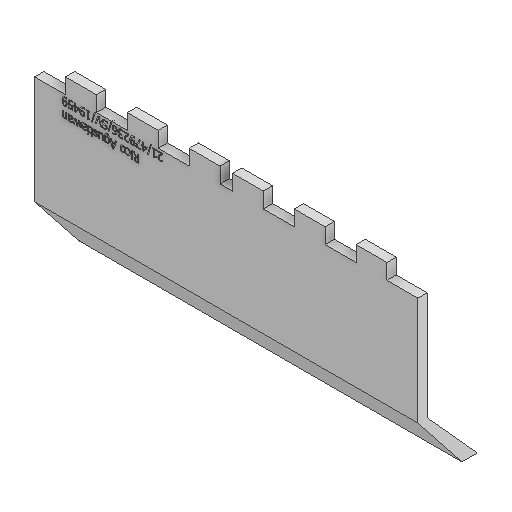
# Autodesk Inventor part: BodyFront
Saved by Autodesk Inventor 2025.2 (Build 292293000, 293)
## iProperties
Created: 2025-06-25
Part Number: BodyFront
Material: Generic
Document SubType Name: Modeling
Designer: ricoa
Density: 1 g/cm^3
Appearance: Default
Author: ricoa
Autodesk Inventor part; units mm, degrees
ref_plane "YZ Plane" through (0, 0, 0) normal (1, 0, 0) x (0, 1, 0)
ref_plane "XZ Plane" through (0, 0, 0) normal (0, 1, 0) x (-1, 0, 0)
sketch "Sketch1" plane through (0, 0, 0) normal (0, 0, 1) x (1, 0, 0)
  line L0 (104, 5) -> (114, 5) projected
  line L1 (84, 5) -> (94, 5) projected
  line L2 (94, 0) -> (104, 0) projected
  line L3 (74, 0) -> (84, 0) projected
  line L4 (64, 5) -> (74, 5) projected
  line L5 (60, 0) -> (64, 0) projected
  line L6 (50, 5) -> (60, 5) projected
  line L7 (40, 0) -> (50, 0) projected
  line L8 (30, 5) -> (40, 5) projected
  line L9 (20, 0) -> (30, 0) projected
  line L10 (10, 5) -> (20, 5) projected
  line L11 (0, 0) -> (10, 0) projected
  line L12 (10, 0) -> (10, 5) projected
  line L13 (20, 5) -> (20, 0) projected
  line L14 (30, 0) -> (30, 5) projected
  line L15 (40, 5) -> (40, 0) projected
  line L16 (50, 0) -> (50, 5) projected
  line L17 (60, 5) -> (60, 0) projected
  line L18 (64, 0) -> (64, 5) projected
  line L19 (84, 0) -> (84, 5) projected
  line L20 (94, 5) -> (94, 0) projected
  line L21 (104, 0) -> (104, 5) projected
  line L22 (114, 5) -> (114, 0) projected
  line L23 (114, 0) -> (124, 0) projected
  line L24 (124, 0) -> (124, -30)
  line L25 (0, -30) -> (0, 0)
  line L26 (74, 5) -> (74, 0) projected
  line L27 (0, -15) -> (124, -15) construction
  line L28 (104, -35) -> (114, -35)
  line L29 (84, -35) -> (94, -35)
  line L30 (94, -30) -> (104, -30)
  line L31 (74, -30) -> (84, -30)
  line L32 (64, -35) -> (74, -35)
  line L33 (60, -30) -> (64, -30)
  line L34 (50, -35) -> (60, -35)
  line L35 (40, -30) -> (50, -30)
  line L36 (30, -35) -> (40, -35)
  line L37 (20, -30) -> (30, -30)
  line L38 (10, -35) -> (20, -35)
  line L39 (0, -30) -> (10, -30)
  line L40 (10, -30) -> (10, -35)
  line L41 (20, -35) -> (20, -30)
  line L42 (30, -30) -> (30, -35)
  line L43 (40, -35) -> (40, -30)
  line L44 (50, -30) -> (50, -35)
  line L45 (60, -35) -> (60, -30)
  line L46 (64, -30) -> (64, -35)
  line L47 (84, -30) -> (84, -35)
  line L48 (94, -35) -> (94, -30)
  line L49 (104, -30) -> (104, -35)
  line L50 (114, -35) -> (114, -30)
  line L51 (114, -30) -> (124, -30)
  line L52 (74, -35) -> (74, -30)
  dimension "d0" = 30
  constraints: 56 end point, 24 symmetric about line, 2 midpoint, 1 vertical
  measures "d0" distance of L23.end L24.end
extrude "Extrusion1" add sketch "Sketch1" against normal blind 3
sketch "Sketch2" plane through (0, 0, 0) normal (0, 0, 1) x (1, 0, 0)
  line L0 (124, -30) -> (124, 0) projected
  line L1 (0, -30) -> (0, 0) projected
  line L2 (124, -30) -> (0, -30)
  line L3 (132.7341, -7.4829) -> (8.7341, -7.4829) construction
  line L4 (8.7341, -7.4829) -> (8.7341, -37.4829) construction
  line L5 (8.7341, -37.4829) -> (132.7341, -37.4829) construction
  line L6 (132.7341, -37.4829) -> (132.7341, -7.4829) construction
  line L7 (31.7814, -4.9264) -> (32.2199, -4.9264)
  line L8 (32.2199, -4.9264) -> (33.0226, -5.9371)
  line L9 (33.0226, -5.9371) -> (33.4096, -5.9371)
  line L10 (33.4096, -5.9371) -> (33.4096, -4.9264)
  line L11 (33.4096, -4.9264) -> (33.7472, -4.9264)
  line L12 (33.7472, -4.9264) -> (33.7472, -7.4664)
  line L13 (33.7472, -7.4664) -> (33.0926, -7.4664)
  spline S0 degree 2 poles (33.0926, -7.4664) (32.8744, -7.4664) (32.5801, -7.4191) (32.4463, -7.3326) knots 0 0 0 1 2 2 2
  spline S1 degree 2 poles (32.4463, -7.3326) (32.3125, -7.2462) (32.1581, -6.9765) (32.1581, -6.7769) knots 0 0 0 1 2 2 2
  spline S2 degree 2 poles (32.1581, -6.7769) (32.1581, -6.499) (32.4422, -6.1223) (32.685, -6.0318) knots 0 0 0 1 2 2 2
  line L14 (32.685, -6.0318) -> (31.7814, -4.9264)
  spline S3 degree 2 poles (32.5101, -6.7501) (32.5101, -6.8613) (32.5883, -7.0321) (32.6706, -7.0877) knots 0 0 0 1 2 2 2
  spline S4 degree 2 poles (32.6706, -7.0877) (32.7427, -7.135) (32.9341, -7.1741) (33.0741, -7.1741) knots 0 0 0 1 2 2 2
  line L15 (33.0741, -7.1741) -> (33.4096, -7.1741)
  line L16 (33.4096, -7.1741) -> (33.4096, -6.2191)
  line L17 (33.4096, -6.2191) -> (33.1132, -6.2191)
  spline S5 degree 2 poles (33.1132, -6.2191) (32.967, -6.2191) (32.7344, -6.2705) (32.6542, -6.3508) knots 0 0 0 1 2 2 2
  spline S6 degree 2 poles (32.6542, -6.3508) (32.5801, -6.4208) (32.5101, -6.6184) (32.5101, -6.7501) knots 0 0 0 1 2 2 2
  line L18 (31.2771, -4.9264) -> (31.5982, -4.9264)
  line L19 (31.5982, -4.9264) -> (31.5982, -6.8325)
  line L20 (31.5982, -6.8325) -> (31.2771, -6.8325)
  line L21 (31.2771, -6.8325) -> (31.2771, -4.9264)
  line L22 (31.2545, -7.1494) -> (31.6188, -7.1494)
  line L23 (31.6188, -7.1494) -> (31.6188, -7.4829)
  line L24 (31.6188, -7.4829) -> (31.2545, -7.4829)
  line L25 (31.2545, -7.4829) -> (31.2545, -7.1494)
  spline S7 degree 2 poles (30.0483, -4.8832) (30.2459, -4.8832) (30.5732, -5.0046) (30.6905, -5.1281) knots 0 0 0 1 2 2 2
  spline S8 degree 2 poles (30.6905, -5.1281) (30.8078, -5.2496) (30.9375, -5.6242) (30.9375, -5.8753) knots 0 0 0 1 2 2 2
  spline S9 degree 2 poles (30.9375, -5.8753) (30.9375, -6.1264) (30.8037, -6.4928) (30.6905, -6.6163) knots 0 0 0 1 2 2 2
  spline S10 degree 2 poles (30.6905, -6.6163) (30.5773, -6.7419) (30.2418, -6.8757) (30.0483, -6.8757) knots 0 0 0 1 2 2 2
  spline S11 degree 2 poles (30.0483, -6.8757) (29.8919, -6.8757) (29.5996, -6.7872) (29.4864, -6.7295) knots 0 0 0 1 2 2 2
  line L26 (29.4864, -6.7295) -> (29.4864, -6.3693)
  line L27 (29.4864, -6.3693) -> (29.5049, -6.3693)
  spline S12 degree 2 poles (29.5049, -6.3693) (29.5399, -6.3981) (29.6469, -6.4722) (29.7231, -6.5114) knots 0 0 0 1 2 2 2
  spline S13 degree 2 poles (29.7231, -6.5114) (29.791, -6.5443) (29.9721, -6.5957) (30.0545, -6.5957) knots 0 0 0 1 2 2 2
  spline S14 degree 2 poles (30.0545, -6.5957) (30.3035, -6.5957) (30.6061, -6.2191) (30.6061, -5.8753) knots 0 0 0 1 2 2 2
  spline S15 degree 2 poles (30.6061, -5.8753) (30.6061, -5.5398) (30.3138, -5.1631) (30.0545, -5.1631) knots 0 0 0 1 2 2 2
  spline S16 degree 2 poles (30.0545, -5.1631) (29.898, -5.1631) (29.614, -5.2928) (29.5049, -5.3937) knots 0 0 0 1 2 2 2
  line L28 (29.5049, -5.3937) -> (29.4864, -5.3937)
  line L29 (29.4864, -5.3937) -> (29.4864, -5.0335)
  spline S17 degree 2 poles (29.4864, -5.0335) (29.5337, -5.0108) (29.6778, -4.947) (29.7354, -4.9326) knots 0 0 0 1 2 2 2
  spline S18 degree 2 poles (29.7354, -4.9326) (29.8178, -4.9079) (29.9474, -4.8832) (30.0483, -4.8832) knots 0 0 0 1 2 2 2
  spline S19 degree 2 poles (27.6277, -5.8794) (27.6277, -5.3978) (28.0908, -4.8729) (28.4778, -4.8729) knots 0 0 0 1 2 2 2
  spline S20 degree 2 poles (28.4778, -4.8729) (28.875, -4.8729) (29.3299, -5.4143) (29.3299, -5.8794) knots 0 0 0 1 2 2 2
  spline S21 degree 2 poles (29.3299, -5.8794) (29.3299, -6.357) (28.8606, -6.886) (28.4778, -6.886) knots 0 0 0 1 2 2 2
  spline S22 degree 2 poles (28.4778, -6.886) (28.0908, -6.886) (27.6277, -6.359) (27.6277, -5.8794) knots 0 0 0 1 2 2 2
  spline S23 degree 2 poles (27.9591, -5.8794) (27.9591, -6.2499) (28.2287, -6.6102) (28.4778, -6.6102) knots 0 0 0 1 2 2 2
  spline S24 degree 2 poles (28.4778, -6.6102) (28.7268, -6.6102) (28.9986, -6.2499) (28.9986, -5.8794) knots 0 0 0 1 2 2 2
  spline S25 degree 2 poles (28.9986, -5.8794) (28.9986, -5.5192) (28.7268, -5.1487) (28.4778, -5.1487) knots 0 0 0 1 2 2 2
  spline S26 degree 2 poles (28.4778, -5.1487) (28.2308, -5.1487) (27.9591, -5.5131) (27.9591, -5.8794) knots 0 0 0 1 2 2 2
  line L30 (26.4565, -4.9264) -> (25.6002, -7.4664)
  line L31 (25.6002, -7.4664) -> (25.1844, -7.4664)
  line L32 (25.1844, -7.4664) -> (24.3282, -4.9264)
  line L33 (24.3282, -4.9264) -> (24.6843, -4.9264)
  line L34 (24.6843, -4.9264) -> (24.9148, -5.6366)
  line L35 (24.9148, -5.6366) -> (25.8843, -5.6366)
  line L36 (25.8843, -5.6366) -> (26.1148, -4.9264)
  line L37 (26.1148, -4.9264) -> (26.4565, -4.9264)
  line L38 (25.0074, -5.9247) -> (25.4006, -7.1206)
  line L39 (25.4006, -7.1206) -> (25.7916, -5.9247)
  line L40 (25.7916, -5.9247) -> (25.0074, -5.9247)
  spline S27 degree 2 poles (24.0441, -4.6218) (24.0112, -4.6074) (23.8856, -4.5621) (23.8053, -4.5436) knots 0 0 0 1 2 2 2
  spline S28 degree 2 poles (23.8053, -4.5436) (23.7168, -4.5209) (23.5666, -4.4942) (23.4781, -4.4942) knots 0 0 0 1 2 2 2
  spline S29 degree 2 poles (23.4781, -4.4942) (23.3299, -4.4942) (23.124, -4.5724) (23.0664, -4.6424) knots 0 0 0 1 2 2 2
  spline S30 degree 2 poles (23.0664, -4.6424) (23.0108, -4.7124) (22.9676, -4.8956) (22.9676, -5.0129) knots 0 0 0 1 2 2 2
  line L41 (22.9676, -5.0129) -> (22.9676, -5.1796)
  spline S31 degree 2 poles (22.9676, -5.1796) (23.0973, -5.0664) (23.3463, -4.9594) (23.5336, -4.9594) knots 0 0 0 1 2 2 2
  spline S32 degree 2 poles (23.5336, -4.9594) (23.8589, -4.9594) (24.2438, -5.4431) (24.2438, -5.898) knots 0 0 0 1 2 2 2
  spline S33 degree 2 poles (24.2438, -5.898) (24.2438, -6.1347) (24.11, -6.5011) (23.9988, -6.6307) knots 0 0 0 1 2 2 2
  spline S34 degree 2 poles (23.9988, -6.6307) (23.8918, -6.7522) (23.5974, -6.886) (23.441, -6.886) knots 0 0 0 1 2 2 2
  spline S35 degree 2 poles (23.441, -6.886) (23.2928, -6.886) (23.0767, -6.816) (22.9676, -6.7522) knots 0 0 0 1 2 2 2
  line L42 (22.9676, -6.7522) -> (22.9491, -6.8325)
  line L43 (22.9491, -6.8325) -> (22.6465, -6.8325)
  line L44 (22.6465, -6.8325) -> (22.6465, -5.1446)
  spline S36 degree 2 poles (22.6465, -5.1446) (22.6465, -4.6588) (23.0685, -4.206) (23.5028, -4.206) knots 0 0 0 1 2 2 2
  spline S37 degree 2 poles (23.5028, -4.206) (23.6427, -4.206) (23.935, -4.2513) (24.0606, -4.2883) knots 0 0 0 1 2 2 2
  line L45 (24.0606, -4.2883) -> (24.0606, -4.6218)
  line L46 (24.0606, -4.6218) -> (24.0441, -4.6218)
  line L47 (22.9676, -5.4431) -> (22.9676, -6.4908)
  spline S38 degree 2 poles (22.9676, -6.4908) (23.087, -6.5484) (23.2887, -6.5978) (23.3896, -6.5978) knots 0 0 0 1 2 2 2
  spline S39 degree 2 poles (23.3896, -6.5978) (23.6324, -6.5978) (23.9124, -6.2397) (23.9124, -5.9041) knots 0 0 0 1 2 2 2
  spline S40 degree 2 poles (23.9124, -5.9041) (23.9124, -5.5872) (23.7004, -5.2558) (23.4616, -5.2558) knots 0 0 0 1 2 2 2
  spline S41 degree 2 poles (23.4616, -5.2558) (23.336, -5.2558) (23.0726, -5.3546) (22.9676, -5.4431) knots 0 0 0 1 2 2 2
  line L48 (20.6993, -4.9264) -> (21.0204, -4.9264)
  line L49 (21.0204, -4.9264) -> (21.0204, -5.1364)
  spline S42 degree 2 poles (21.0204, -5.1364) (21.1686, -5.0067) (21.4341, -4.8729) (21.5988, -4.8729) knots 0 0 0 1 2 2 2
  spline S43 degree 2 poles (21.5988, -4.8729) (21.7223, -4.8729) (21.9425, -4.9552) (22.0228, -5.0438) knots 0 0 0 1 2 2 2
  spline S44 degree 2 poles (22.0228, -5.0438) (22.1051, -5.1323) (22.1957, -5.4019) (22.1957, -5.5954) knots 0 0 0 1 2 2 2
  line L50 (22.1957, -5.5954) -> (22.1957, -6.8325)
  line L51 (22.1957, -6.8325) -> (21.8746, -6.8325)
  line L52 (21.8746, -6.8325) -> (21.8746, -5.7456)
  spline S45 degree 2 poles (21.8746, -5.7456) (21.8746, -5.5933) (21.852, -5.3937) (21.8129, -5.3196) knots 0 0 0 1 2 2 2
  spline S46 degree 2 poles (21.8129, -5.3196) (21.7738, -5.2455) (21.64, -5.1775) (21.5144, -5.1775) knots 0 0 0 1 2 2 2
  spline S47 degree 2 poles (21.5144, -5.1775) (21.3971, -5.1775) (21.1315, -5.3113) (21.0204, -5.4081) knots 0 0 0 1 2 2 2
  line L53 (21.0204, -5.4081) -> (21.0204, -6.8325)
  line L54 (21.0204, -6.8325) -> (20.6993, -6.8325)
  line L55 (20.6993, -6.8325) -> (20.6993, -4.9264)
  spline S48 degree 2 poles (19.7195, -4.8811) (19.9109, -4.8811) (20.2423, -4.9841) (20.3514, -5.0417) knots 0 0 0 1 2 2 2
  line L56 (20.3514, -5.0417) -> (20.3514, -5.4019)
  line L57 (20.3514, -5.4019) -> (20.335, -5.4019)
  spline S49 degree 2 poles (20.335, -5.4019) (20.2938, -5.369) (20.1827, -5.2908) (20.09, -5.2475) knots 0 0 0 1 2 2 2
  spline S50 degree 2 poles (20.09, -5.2475) (20.0097, -5.2084) (19.8121, -5.1508) (19.7072, -5.1508) knots 0 0 0 1 2 2 2
  spline S51 degree 2 poles (19.7072, -5.1508) (19.631, -5.1508) (19.4561, -5.1858) (19.4149, -5.2146) knots 0 0 0 1 2 2 2
  spline S52 degree 2 poles (19.4149, -5.2146) (19.3552, -5.2537) (19.3017, -5.3422) (19.3017, -5.4328) knots 0 0 0 1 2 2 2
  spline S53 degree 2 poles (19.3017, -5.4328) (19.3017, -5.546) (19.4252, -5.6633) (19.5837, -5.7024) knots 0 0 0 1 2 2 2
  spline S54 degree 2 poles (19.5837, -5.7024) (19.6454, -5.7168) (19.843, -5.758) (19.9274, -5.7806) knots 0 0 0 1 2 2 2
  spline S55 degree 2 poles (19.9274, -5.7806) (20.1456, -5.8444) (20.3432, -6.1079) (20.3432, -6.2952) knots 0 0 0 1 2 2 2
  spline S56 degree 2 poles (20.3432, -6.2952) (20.3432, -6.5546) (19.9542, -6.8777) (19.6331, -6.8777) knots 0 0 0 1 2 2 2
  spline S57 degree 2 poles (19.6331, -6.8777) (19.4746, -6.8777) (19.1535, -6.7995) (19.0444, -6.7398) knots 0 0 0 1 2 2 2
  line L58 (19.0444, -6.7398) -> (19.0444, -6.3961)
  line L59 (19.0444, -6.3961) -> (19.0609, -6.3961)
  spline S58 degree 2 poles (19.0609, -6.3961) (19.1844, -6.4949) (19.4849, -6.6081) (19.6392, -6.6081) knots 0 0 0 1 2 2 2
  spline S59 degree 2 poles (19.6392, -6.6081) (19.7977, -6.6081) (20.0159, -6.4743) (20.0159, -6.3405) knots 0 0 0 1 2 2 2
  spline S60 degree 2 poles (20.0159, -6.3405) (20.0159, -6.2191) (19.8862, -6.1017) (19.7422, -6.0647) knots 0 0 0 1 2 2 2
  spline S61 degree 2 poles (19.7422, -6.0647) (19.6722, -6.0462) (19.4952, -6.0091) (19.3984, -5.9865) knots 0 0 0 1 2 2 2
  spline S62 degree 2 poles (19.3984, -5.9865) (19.1885, -5.933) (18.9744, -5.688) (18.9744, -5.476) knots 0 0 0 1 2 2 2
  spline S63 degree 2 poles (18.9744, -5.476) (18.9744, -5.3525) (19.0711, -5.1343) (19.1658, -5.054) knots 0 0 0 1 2 2 2
  spline S64 degree 2 poles (19.1658, -5.054) (19.2667, -4.9697) (19.524, -4.8811) (19.7195, -4.8811) knots 0 0 0 1 2 2 2
  spline S65 degree 2 poles (18.0996, -4.8894) (18.361, -4.8894) (18.6554, -5.1878) (18.6554, -5.511) knots 0 0 0 1 2 2 2
  line L60 (18.6554, -5.511) -> (18.6554, -6.5669)
  line L61 (18.6554, -6.5669) -> (18.8715, -6.5669)
  line L62 (18.8715, -6.5669) -> (18.8715, -6.8325)
  line L63 (18.8715, -6.8325) -> (18.6554, -6.8325)
  line L64 (18.6554, -6.8325) -> (18.6554, -7.38)
  line L65 (18.6554, -7.38) -> (18.3343, -7.38)
  line L66 (18.3343, -7.38) -> (18.3343, -6.8325)
  line L67 (18.3343, -6.8325) -> (17.7435, -6.8325)
  line L68 (17.7435, -6.8325) -> (17.7435, -6.5669)
  line L69 (17.7435, -6.5669) -> (18.3343, -6.5669)
  line L70 (18.3343, -6.5669) -> (18.3343, -5.6592)
  spline S66 degree 2 poles (18.3343, -5.6592) (18.3343, -5.5151) (18.324, -5.3566) (18.289, -5.2887) knots 0 0 0 1 2 2 2
  spline S67 degree 2 poles (18.289, -5.2887) (18.2602, -5.229) (18.1305, -5.1693) (18.0193, -5.1693) knots 0 0 0 1 2 2 2
  spline S68 degree 2 poles (18.0193, -5.1693) (17.9411, -5.1693) (17.795, -5.2167) (17.762, -5.2311) knots 0 0 0 1 2 2 2
  line L71 (17.762, -5.2311) -> (17.7435, -5.2311)
  line L72 (17.7435, -5.2311) -> (17.7435, -4.9429)
  spline S69 degree 2 poles (17.7435, -4.9429) (17.8341, -4.9182) (18.0193, -4.8894) (18.0996, -4.8894) knots 0 0 0 1 2 2 2
  line L73 (17.1795, -4.9264) -> (17.5006, -4.9264)
  line L74 (17.5006, -4.9264) -> (17.5006, -6.8325)
  line L75 (17.5006, -6.8325) -> (17.1795, -6.8325)
  line L76 (17.1795, -6.8325) -> (17.1795, -4.9264)
  line L77 (17.1569, -7.1494) -> (17.5212, -7.1494)
  line L78 (17.5212, -7.1494) -> (17.5212, -7.4829)
  line L79 (17.5212, -7.4829) -> (17.1569, -7.4829)
  line L80 (17.1569, -7.4829) -> (17.1569, -7.1494)
  spline S70 degree 2 poles (15.6461, -5.1281) (15.6852, -5.0993) (15.8169, -4.9964) (15.8786, -4.9655) knots 0 0 0 1 2 2 2
  spline S71 degree 2 poles (15.8786, -4.9655) (15.963, -4.9203) (16.1215, -4.8729) (16.2656, -4.8729) knots 0 0 0 1 2 2 2
  spline S72 degree 2 poles (16.2656, -4.8729) (16.3829, -4.8729) (16.595, -4.9614) (16.6752, -5.0417) knots 0 0 0 1 2 2 2
  spline S73 degree 2 poles (16.6752, -5.0417) (16.7514, -5.1199) (16.844, -5.3504) (16.844, -5.4781) knots 0 0 0 1 2 2 2
  spline S74 degree 2 poles (16.844, -5.4781) (16.844, -5.6757) (16.6773, -5.9556) (16.4962, -6.0359) knots 0 0 0 1 2 2 2
  spline S75 degree 2 poles (16.4962, -6.0359) (16.3356, -6.11) (15.8992, -6.1656) (15.6461, -6.18) knots 0 0 0 1 2 2 2
  line L81 (15.6461, -6.18) -> (15.6461, -6.2417)
  spline S76 degree 2 poles (15.6461, -6.2417) (15.6461, -6.3529) (15.714, -6.4908) (15.7757, -6.5299) knots 0 0 0 1 2 2 2
  spline S77 degree 2 poles (15.7757, -6.5299) (15.8375, -6.569) (16.0145, -6.5937) (16.1092, -6.5937) knots 0 0 0 1 2 2 2
  spline S78 degree 2 poles (16.1092, -6.5937) (16.2203, -6.5937) (16.5209, -6.5278) (16.6711, -6.464) knots 0 0 0 1 2 2 2
  line L82 (16.6711, -6.464) -> (16.6896, -6.464)
  line L83 (16.6896, -6.464) -> (16.6896, -6.7913)
  spline S79 degree 2 poles (16.6896, -6.7913) (16.6011, -6.816) (16.2697, -6.8777) (16.1071, -6.8777) knots 0 0 0 1 2 2 2
  spline S80 degree 2 poles (16.1071, -6.8777) (15.9095, -6.8777) (15.6399, -6.816) (15.5328, -6.7357) knots 0 0 0 1 2 2 2
  spline S81 degree 2 poles (15.5328, -6.7357) (15.4279, -6.6575) (15.325, -6.4084) (15.325, -6.2294) knots 0 0 0 1 2 2 2
  line L84 (15.325, -6.2294) -> (15.325, -4.9264)
  line L85 (15.325, -4.9264) -> (15.6461, -4.9264)
  line L86 (15.6461, -4.9264) -> (15.6461, -5.1281)
  line L87 (15.6461, -5.3957) -> (15.6461, -5.9247)
  spline S82 degree 2 poles (15.6461, -5.9247) (15.7613, -5.9144) (16.1092, -5.8794) (16.2183, -5.8465) knots 0 0 0 1 2 2 2
  spline S83 degree 2 poles (16.2183, -5.8465) (16.3459, -5.8074) (16.5126, -5.6448) (16.5126, -5.5007) knots 0 0 0 1 2 2 2
  spline S84 degree 2 poles (16.5126, -5.5007) (16.5126, -5.336) (16.3274, -5.1693) (16.1503, -5.1693) knots 0 0 0 1 2 2 2
  spline S85 degree 2 poles (16.1503, -5.1693) (16.0001, -5.1693) (15.7531, -5.299) (15.6461, -5.3957) knots 0 0 0 1 2 2 2
  line L88 (12.5647, -6.8325) -> (13.0484, -4.9264)
  line L89 (13.0484, -4.9264) -> (13.3448, -4.9264)
  line L90 (13.3448, -4.9264) -> (13.81, -6.3961)
  line L91 (13.81, -6.3961) -> (14.2731, -4.9264)
  line L92 (14.2731, -4.9264) -> (14.5675, -4.9264)
  line L93 (14.5675, -4.9264) -> (15.0553, -6.8325)
  line L94 (15.0553, -6.8325) -> (14.7219, -6.8325)
  line L95 (14.7219, -6.8325) -> (14.3843, -5.3566)
  line L96 (14.3843, -5.3566) -> (13.9335, -6.8325)
  line L97 (13.9335, -6.8325) -> (13.668, -6.8325)
  line L98 (13.668, -6.8325) -> (13.2049, -5.3566)
  line L99 (13.2049, -5.3566) -> (12.8879, -6.8325)
  line L100 (12.8879, -6.8325) -> (12.5647, -6.8325)
  spline S86 degree 2 poles (11.2206, -5.1281) (11.2597, -5.0993) (11.3915, -4.9964) (11.4532, -4.9655) knots 0 0 0 1 2 2 2
  spline S87 degree 2 poles (11.4532, -4.9655) (11.5376, -4.9203) (11.6961, -4.8729) (11.8402, -4.8729) knots 0 0 0 1 2 2 2
  spline S88 degree 2 poles (11.8402, -4.8729) (11.9575, -4.8729) (12.1695, -4.9614) (12.2498, -5.0417) knots 0 0 0 1 2 2 2
  spline S89 degree 2 poles (12.2498, -5.0417) (12.3259, -5.1199) (12.4186, -5.3504) (12.4186, -5.4781) knots 0 0 0 1 2 2 2
  spline S90 degree 2 poles (12.4186, -5.4781) (12.4186, -5.6757) (12.2518, -5.9556) (12.0707, -6.0359) knots 0 0 0 1 2 2 2
  spline S91 degree 2 poles (12.0707, -6.0359) (11.9102, -6.11) (11.4738, -6.1656) (11.2206, -6.18) knots 0 0 0 1 2 2 2
  line L101 (11.2206, -6.18) -> (11.2206, -6.2417)
  spline S92 degree 2 poles (11.2206, -6.2417) (11.2206, -6.3529) (11.2885, -6.4908) (11.3503, -6.5299) knots 0 0 0 1 2 2 2
  spline S93 degree 2 poles (11.3503, -6.5299) (11.412, -6.569) (11.5891, -6.5937) (11.6837, -6.5937) knots 0 0 0 1 2 2 2
  spline S94 degree 2 poles (11.6837, -6.5937) (11.7949, -6.5937) (12.0954, -6.5278) (12.2457, -6.464) knots 0 0 0 1 2 2 2
  line L102 (12.2457, -6.464) -> (12.2642, -6.464)
  line L103 (12.2642, -6.464) -> (12.2642, -6.7913)
  spline S95 degree 2 poles (12.2642, -6.7913) (12.1757, -6.816) (11.8443, -6.8777) (11.6817, -6.8777) knots 0 0 0 1 2 2 2
  spline S96 degree 2 poles (11.6817, -6.8777) (11.4841, -6.8777) (11.2144, -6.816) (11.1074, -6.7357) knots 0 0 0 1 2 2 2
  spline S97 degree 2 poles (11.1074, -6.7357) (11.0024, -6.6575) (10.8995, -6.4084) (10.8995, -6.2294) knots 0 0 0 1 2 2 2
  line L104 (10.8995, -6.2294) -> (10.8995, -4.9264)
  line L105 (10.8995, -4.9264) -> (11.2206, -4.9264)
  line L106 (11.2206, -4.9264) -> (11.2206, -5.1281)
  line L107 (11.2206, -5.3957) -> (11.2206, -5.9247)
  spline S98 degree 2 poles (11.2206, -5.9247) (11.3359, -5.9144) (11.6837, -5.8794) (11.7928, -5.8465) knots 0 0 0 1 2 2 2
  spline S99 degree 2 poles (11.7928, -5.8465) (11.9204, -5.8074) (12.0872, -5.6448) (12.0872, -5.5007) knots 0 0 0 1 2 2 2
  spline S100 degree 2 poles (12.0872, -5.5007) (12.0872, -5.336) (11.9019, -5.1693) (11.7249, -5.1693) knots 0 0 0 1 2 2 2
  spline S101 degree 2 poles (11.7249, -5.1693) (11.5746, -5.1693) (11.3276, -5.299) (11.2206, -5.3957) knots 0 0 0 1 2 2 2
  line L108 (8.9523, -4.9264) -> (9.2734, -4.9264)
  line L109 (9.2734, -4.9264) -> (9.2734, -6.0132)
  spline S102 degree 2 poles (9.2734, -6.0132) (9.2734, -6.145) (9.2981, -6.3714) (9.3352, -6.4393) knots 0 0 0 1 2 2 2
  spline S103 degree 2 poles (9.3352, -6.4393) (9.3743, -6.5114) (9.5142, -6.5813) (9.6336, -6.5813) knots 0 0 0 1 2 2 2
  spline S104 degree 2 poles (9.6336, -6.5813) (9.753, -6.5813) (10.0062, -6.4537) (10.1276, -6.3508) knots 0 0 0 1 2 2 2
  line L110 (10.1276, -6.3508) -> (10.1276, -4.9264)
  line L111 (10.1276, -4.9264) -> (10.4487, -4.9264)
  line L112 (10.4487, -4.9264) -> (10.4487, -6.8325)
  line L113 (10.4487, -6.8325) -> (10.1276, -6.8325)
  line L114 (10.1276, -6.8325) -> (10.1276, -6.6204)
  spline S105 degree 2 poles (10.1276, -6.6204) (9.9835, -6.7501) (9.7057, -6.886) (9.5492, -6.886) knots 0 0 0 1 2 2 2
  spline S106 degree 2 poles (9.5492, -6.886) (9.2693, -6.886) (8.9523, -6.5155) (8.9523, -6.1635) knots 0 0 0 1 2 2 2
  line L115 (8.9523, -6.1635) -> (8.9523, -4.9264)
  line L116 (39.7987, -0.7444) -> (41.3651, -0.7444)
  line L117 (41.3651, -0.7444) -> (41.3651, -1.1046)
  spline S107 degree 2 poles (41.3651, -1.1046) (41.1963, -1.2631) (40.8958, -1.5574) (40.7517, -1.7159) knots 0 0 0 1 2 2 2
  spline S108 degree 2 poles (40.7517, -1.7159) (40.4615, -2.035) (40.2495, -2.4178) (40.2495, -2.6216) knots 0 0 0 1 2 2 2
  spline S109 degree 2 poles (40.2495, -2.6216) (40.2495, -2.7286) (40.3153, -2.8892) (40.375, -2.9406) knots 0 0 0 1 2 2 2
  spline S110 degree 2 poles (40.375, -2.9406) (40.4347, -2.9921) (40.5912, -3.0436) (40.6858, -3.0436) knots 0 0 0 1 2 2 2
  spline S111 degree 2 poles (40.6858, -3.0436) (40.7764, -3.0436) (40.9617, -2.9983) (41.0461, -2.9633) knots 0 0 0 1 2 2 2
  spline S112 degree 2 poles (41.0461, -2.9633) (41.1181, -2.9345) (41.2519, -2.8521) (41.2931, -2.8233) knots 0 0 0 1 2 2 2
  line L118 (41.2931, -2.8233) -> (41.3116, -2.8233)
  line L119 (41.3116, -2.8233) -> (41.3116, -3.1856)
  spline S113 degree 2 poles (41.3116, -3.1856) (41.2066, -3.237) (40.8299, -3.3379) (40.6611, -3.3379) knots 0 0 0 1 2 2 2
  spline S114 degree 2 poles (40.6611, -3.3379) (40.3051, -3.3379) (39.9037, -2.9612) (39.9037, -2.6401) knots 0 0 0 1 2 2 2
  spline S115 degree 2 poles (39.9037, -2.6401) (39.9037, -2.4899) (39.9737, -2.2387) (40.0354, -2.1317) knots 0 0 0 1 2 2 2
  spline S116 degree 2 poles (40.0354, -2.1317) (40.0972, -2.0206) (40.2762, -1.8024) (40.375, -1.6974) knots 0 0 0 1 2 2 2
  spline S117 degree 2 poles (40.375, -1.6974) (40.5356, -1.5224) (40.9287, -1.1478) (41.0461, -1.0387) knots 0 0 0 1 2 2 2
  line L120 (41.0461, -1.0387) -> (39.7987, -1.0387)
  line L121 (39.7987, -1.0387) -> (39.7987, -0.7444)
  line L122 (38.0203, -0.7444) -> (39.2594, -0.7444)
  line L123 (39.2594, -0.7444) -> (39.2594, -1.0037)
  line L124 (39.2594, -1.0037) -> (38.7983, -1.0037)
  line L125 (38.7983, -1.0037) -> (38.7983, -2.706)
  line L126 (38.7983, -2.706) -> (39.2594, -2.706)
  line L127 (39.2594, -2.706) -> (39.2594, -2.9386)
  spline S118 degree 2 poles (39.2594, -2.9386) (38.998, -2.9386) (38.751, -3.0868) (38.7345, -3.2926) knots 0 0 0 1 2 2 2
  line L128 (38.7345, -3.2926) -> (38.4711, -3.2926)
  line L129 (38.4711, -3.2926) -> (38.4711, -1.0037)
  line L130 (38.4711, -1.0037) -> (38.0203, -1.0037)
  line L131 (38.0203, -1.0037) -> (38.0203, -0.7444)
  line L132 (36.4971, -3.3976) -> (37.4913, -0.1927)
  line L133 (37.4913, -0.1927) -> (37.7795, -0.1927)
  line L134 (37.7795, -0.1927) -> (36.7894, -3.3976)
  line L135 (36.7894, -3.3976) -> (36.4971, -3.3976)
  line L136 (34.5828, -1.6171) -> (34.8854, -1.6171)
  line L137 (34.8854, -1.6171) -> (34.8854, -0.7444)
  line L138 (34.8854, -0.7444) -> (35.2127, -0.7444)
  line L139 (35.2127, -0.7444) -> (35.2127, -1.6171)
  line L140 (35.2127, -1.6171) -> (36.3345, -1.6171)
  line L141 (36.3345, -1.6171) -> (36.3345, -1.9753)
  line L142 (36.3345, -1.9753) -> (35.1983, -3.2844)
  line L143 (35.1983, -3.2844) -> (34.8854, -3.2844)
  line L144 (34.8854, -3.2844) -> (34.8854, -1.8909)
  line L145 (34.8854, -1.8909) -> (34.5828, -1.8909)
  line L146 (34.5828, -1.8909) -> (34.5828, -1.6171)
  line L147 (35.2127, -1.8909) -> (35.2127, -2.883)
  line L148 (35.2127, -2.883) -> (36.0669, -1.8909)
  line L149 (36.0669, -1.8909) -> (35.2127, -1.8909)
  line L150 (32.7159, -2.9036) -> (33.8151, -0.7444)
  line L151 (33.8151, -0.7444) -> (34.1774, -0.7444)
  line L152 (34.1774, -0.7444) -> (33.0164, -2.9859)
  line L153 (33.0164, -2.9859) -> (34.3276, -2.9859)
  line L154 (34.3276, -2.9859) -> (34.3276, -3.2844)
  line L155 (34.3276, -3.2844) -> (32.7159, -3.2844)
  line L156 (32.7159, -3.2844) -> (32.7159, -2.9036)
  spline S119 degree 2 poles (32.4751, -2.459) (32.4751, -2.6545) (32.3475, -2.9797) (32.2363, -3.0971) knots 0 0 0 1 2 2 2
  spline S120 degree 2 poles (32.2363, -3.0971) (32.1314, -3.2103) (31.8247, -3.3358) (31.6682, -3.3358) knots 0 0 0 1 2 2 2
  spline S121 degree 2 poles (31.6682, -3.3358) (31.4933, -3.3358) (31.2092, -3.2185) (31.1042, -3.1074) knots 0 0 0 1 2 2 2
  spline S122 degree 2 poles (31.1042, -3.1074) (30.9725, -2.9674) (30.8284, -2.5146) (30.8284, -2.1667) knots 0 0 0 1 2 2 2
  spline S123 degree 2 poles (30.8284, -2.1667) (30.8284, -1.8518) (30.9704, -1.2878) (31.1084, -1.1005) knots 0 0 0 1 2 2 2
  spline S124 degree 2 poles (31.1084, -1.1005) (31.2545, -0.9029) (31.6662, -0.695) (31.9667, -0.695) knots 0 0 0 1 2 2 2
  spline S125 degree 2 poles (31.9667, -0.695) (32.0346, -0.695) (32.189, -0.7094) (32.2549, -0.73) knots 0 0 0 1 2 2 2
  line L157 (32.2549, -0.73) -> (32.2549, -1.0573)
  line L158 (32.2549, -1.0573) -> (32.2384, -1.0573)
  spline S126 degree 2 poles (32.2384, -1.0573) (32.1952, -1.0326) (32.014, -0.9893) (31.9214, -0.9893) knots 0 0 0 1 2 2 2
  spline S127 degree 2 poles (31.9214, -0.9893) (31.588, -0.9893) (31.2072, -1.4298) (31.1804, -1.8374) knots 0 0 0 1 2 2 2
  spline S128 degree 2 poles (31.1804, -1.8374) (31.3162, -1.7447) (31.5633, -1.6603) (31.7094, -1.6603) knots 0 0 0 1 2 2 2
  spline S129 degree 2 poles (31.7094, -1.6603) (31.8494, -1.6603) (32.082, -1.7221) (32.1993, -1.8106) knots 0 0 0 1 2 2 2
  spline S130 degree 2 poles (32.1993, -1.8106) (32.3351, -1.9156) (32.4751, -2.2346) (32.4751, -2.459) knots 0 0 0 1 2 2 2
  spline S131 degree 2 poles (31.1722, -2.2429) (31.1722, -2.5002) (31.2668, -2.8254) (31.3512, -2.9139) knots 0 0 0 1 2 2 2
  spline S132 degree 2 poles (31.3512, -2.9139) (31.4253, -2.9962) (31.5797, -3.058) (31.6703, -3.058) knots 0 0 0 1 2 2 2
  spline S133 degree 2 poles (31.6703, -3.058) (31.8802, -3.058) (32.1293, -2.7574) (32.1293, -2.4734) knots 0 0 0 1 2 2 2
  spline S134 degree 2 poles (32.1293, -2.4734) (32.1293, -2.3128) (32.047, -2.105) (31.9564, -2.0309) knots 0 0 0 1 2 2 2
  spline S135 degree 2 poles (31.9564, -2.0309) (31.8905, -1.9773) (31.7279, -1.9423) (31.6332, -1.9423) knots 0 0 0 1 2 2 2
  spline S136 degree 2 poles (31.6332, -1.9423) (31.5241, -1.9423) (31.273, -2.0185) (31.1783, -2.0823) knots 0 0 0 1 2 2 2
  spline S137 degree 2 poles (31.1783, -2.0823) (31.1763, -2.107) (31.1722, -2.1914) (31.1722, -2.2429) knots 0 0 0 1 2 2 2
  line L159 (28.9327, -0.7444) -> (30.4991, -0.7444)
  line L160 (30.4991, -0.7444) -> (30.4991, -1.1046)
  spline S138 degree 2 poles (30.4991, -1.1046) (30.3303, -1.2631) (30.0298, -1.5574) (29.8857, -1.7159) knots 0 0 0 1 2 2 2
  spline S139 degree 2 poles (29.8857, -1.7159) (29.5955, -2.035) (29.3835, -2.4178) (29.3835, -2.6216) knots 0 0 0 1 2 2 2
  spline S140 degree 2 poles (29.3835, -2.6216) (29.3835, -2.7286) (29.4493, -2.8892) (29.509, -2.9406) knots 0 0 0 1 2 2 2
  spline S141 degree 2 poles (29.509, -2.9406) (29.5687, -2.9921) (29.7251, -3.0436) (29.8198, -3.0436) knots 0 0 0 1 2 2 2
  spline S142 degree 2 poles (29.8198, -3.0436) (29.9104, -3.0436) (30.0956, -2.9983) (30.18, -2.9633) knots 0 0 0 1 2 2 2
  spline S143 degree 2 poles (30.18, -2.9633) (30.2521, -2.9345) (30.3859, -2.8521) (30.427, -2.8233) knots 0 0 0 1 2 2 2
  line L161 (30.427, -2.8233) -> (30.4456, -2.8233)
  line L162 (30.4456, -2.8233) -> (30.4456, -3.1856)
  spline S144 degree 2 poles (30.4456, -3.1856) (30.3406, -3.237) (29.9639, -3.3379) (29.7951, -3.3379) knots 0 0 0 1 2 2 2
  spline S145 degree 2 poles (29.7951, -3.3379) (29.439, -3.3379) (29.0377, -2.9612) (29.0377, -2.6401) knots 0 0 0 1 2 2 2
  spline S146 degree 2 poles (29.0377, -2.6401) (29.0377, -2.4899) (29.1076, -2.2387) (29.1694, -2.1317) knots 0 0 0 1 2 2 2
  spline S147 degree 2 poles (29.1694, -2.1317) (29.2311, -2.0206) (29.4102, -1.8024) (29.509, -1.6974) knots 0 0 0 1 2 2 2
  spline S148 degree 2 poles (29.509, -1.6974) (29.6696, -1.5224) (30.0627, -1.1478) (30.18, -1.0387) knots 0 0 0 1 2 2 2
  line L163 (30.18, -1.0387) -> (28.9327, -1.0387)
  line L164 (28.9327, -1.0387) -> (28.9327, -0.7444)
  spline S149 degree 2 poles (27.9076, -3.0436) (28.0003, -3.0436) (28.1834, -2.9983) (28.272, -2.9633) knots 0 0 0 1 2 2 2
  spline S150 degree 2 poles (28.272, -2.9633) (28.3543, -2.9283) (28.4757, -2.8542) (28.5231, -2.8213) knots 0 0 0 1 2 2 2
  line L165 (28.5231, -2.8213) -> (28.5437, -2.8213)
  line L166 (28.5437, -2.8213) -> (28.5437, -3.1815)
  spline S151 degree 2 poles (28.5437, -3.1815) (28.4325, -3.2412) (28.0517, -3.3379) (27.8809, -3.3379) knots 0 0 0 1 2 2 2
  spline S152 degree 2 poles (27.8809, -3.3379) (27.708, -3.3379) (27.4507, -3.2679) (27.3457, -3.1938) knots 0 0 0 1 2 2 2
  spline S153 degree 2 poles (27.3457, -3.1938) (27.2345, -3.1135) (27.1193, -2.8809) (27.1193, -2.7245) knots 0 0 0 1 2 2 2
  spline S154 degree 2 poles (27.1193, -2.7245) (27.1193, -2.5146) (27.3951, -2.1976) (27.5886, -2.1564) knots 0 0 0 1 2 2 2
  line L167 (27.5886, -2.1564) -> (27.5886, -2.1317)
  spline S155 degree 2 poles (27.5886, -2.1317) (27.5083, -2.1152) (27.3251, -2.0411) (27.2469, -1.967) knots 0 0 0 1 2 2 2
  spline S156 degree 2 poles (27.2469, -1.967) (27.1687, -1.895) (27.0699, -1.6645) (27.0699, -1.4977) knots 0 0 0 1 2 2 2
  spline S157 degree 2 poles (27.0699, -1.4977) (27.0699, -1.3269) (27.1872, -1.0367) (27.2942, -0.9255) knots 0 0 0 1 2 2 2
  spline S158 degree 2 poles (27.2942, -0.9255) (27.4054, -0.8103) (27.7203, -0.6909) (27.92, -0.6909) knots 0 0 0 1 2 2 2
  spline S159 degree 2 poles (27.92, -0.6909) (28.1114, -0.6909) (28.486, -0.7835) (28.6136, -0.8473) knots 0 0 0 1 2 2 2
  line L168 (28.6136, -0.8473) -> (28.6136, -1.2075)
  line L169 (28.6136, -1.2075) -> (28.5889, -1.2075)
  spline S160 degree 2 poles (28.5889, -1.2075) (28.4819, -1.1293) (28.1196, -0.9852) (27.9406, -0.9852) knots 0 0 0 1 2 2 2
  spline S161 degree 2 poles (27.9406, -0.9852) (27.8356, -0.9852) (27.6256, -1.0511) (27.5556, -1.1272) knots 0 0 0 1 2 2 2
  spline S162 degree 2 poles (27.5556, -1.1272) (27.4877, -1.2034) (27.4157, -1.3845) (27.4157, -1.5224) knots 0 0 0 1 2 2 2
  spline S163 degree 2 poles (27.4157, -1.5224) (27.4157, -1.6603) (27.496, -1.8394) (27.568, -1.8909) knots 0 0 0 1 2 2 2
  spline S164 degree 2 poles (27.568, -1.8909) (27.64, -1.9423) (27.8356, -1.9814) (27.9509, -1.9814) knots 0 0 0 1 2 2 2
  line L170 (27.9509, -1.9814) -> (28.0949, -1.9814)
  line L171 (28.0949, -1.9814) -> (28.0949, -2.2634)
  line L172 (28.0949, -2.2634) -> (27.9817, -2.2634)
  spline S165 degree 2 poles (27.9817, -2.2634) (27.7533, -2.2634) (27.4651, -2.4816) (27.4651, -2.6895) knots 0 0 0 1 2 2 2
  spline S166 degree 2 poles (27.4651, -2.6895) (27.4651, -2.7863) (27.5392, -2.9242) (27.5989, -2.9653) knots 0 0 0 1 2 2 2
  spline S167 degree 2 poles (27.5989, -2.9653) (27.6627, -3.0086) (27.8191, -3.0436) (27.9076, -3.0436) knots 0 0 0 1 2 2 2
  spline S168 degree 2 poles (25.0815, -1.5677) (25.0815, -1.3722) (25.2112, -1.0408) (25.3203, -0.9296) knots 0 0 0 1 2 2 2
  spline S169 degree 2 poles (25.3203, -0.9296) (25.4335, -0.8123) (25.7175, -0.6909) (25.8884, -0.6909) knots 0 0 0 1 2 2 2
  spline S170 degree 2 poles (25.8884, -0.6909) (26.0592, -0.6909) (26.3412, -0.8061) (26.4483, -0.9214) knots 0 0 0 1 2 2 2
  spline S171 degree 2 poles (26.4483, -0.9214) (26.58, -1.0593) (26.7282, -1.5224) (26.7282, -1.86) knots 0 0 0 1 2 2 2
  spline S172 degree 2 poles (26.7282, -1.86) (26.7282, -2.1914) (26.5923, -2.7245) (26.4503, -2.9221) knots 0 0 0 1 2 2 2
  spline S173 degree 2 poles (26.4503, -2.9221) (26.3124, -3.1156) (25.876, -3.3317) (25.5899, -3.3317) knots 0 0 0 1 2 2 2
  spline S174 degree 2 poles (25.5899, -3.3317) (25.5055, -3.3317) (25.3573, -3.3153) (25.3018, -3.2967) knots 0 0 0 1 2 2 2
  line L173 (25.3018, -3.2967) -> (25.3018, -2.9695)
  line L174 (25.3018, -2.9695) -> (25.3162, -2.9695)
  spline S175 degree 2 poles (25.3162, -2.9695) (25.3635, -2.9942) (25.5364, -3.0374) (25.6352, -3.0374) knots 0 0 0 1 2 2 2
  spline S176 degree 2 poles (25.6352, -3.0374) (25.9522, -3.0374) (26.3412, -2.6092) (26.3783, -2.1893) knots 0 0 0 1 2 2 2
  spline S177 degree 2 poles (26.3783, -2.1893) (26.2568, -2.2737) (26.0016, -2.3664) (25.8493, -2.3664) knots 0 0 0 1 2 2 2
  spline S178 degree 2 poles (25.8493, -2.3664) (25.7011, -2.3664) (25.4788, -2.3067) (25.3573, -2.2161) knots 0 0 0 1 2 2 2
  spline S179 degree 2 poles (25.3573, -2.2161) (25.2174, -2.1111) (25.0815, -1.7859) (25.0815, -1.5677) knots 0 0 0 1 2 2 2
  spline S180 degree 2 poles (25.4273, -1.5533) (25.4273, -1.7097) (25.5097, -1.9218) (25.6002, -1.9959) knots 0 0 0 1 2 2 2
  spline S181 degree 2 poles (25.6002, -1.9959) (25.6681, -2.0494) (25.8369, -2.0844) (25.9254, -2.0844) knots 0 0 0 1 2 2 2
  spline S182 degree 2 poles (25.9254, -2.0844) (26.0448, -2.0844) (26.2692, -2.0123) (26.3783, -1.9444) knots 0 0 0 1 2 2 2
  spline S183 degree 2 poles (26.3783, -1.9444) (26.3803, -1.9073) (26.3845, -1.8374) (26.3845, -1.7838) knots 0 0 0 1 2 2 2
  spline S184 degree 2 poles (26.3845, -1.7838) (26.3845, -1.5204) (26.2815, -1.1972) (26.2033, -1.1128) knots 0 0 0 1 2 2 2
  spline S185 degree 2 poles (26.2033, -1.1128) (26.1313, -1.0326) (25.9748, -0.9687) (25.8863, -0.9687) knots 0 0 0 1 2 2 2
  spline S186 degree 2 poles (25.8863, -0.9687) (25.6805, -0.9687) (25.4273, -1.261) (25.4273, -1.5533) knots 0 0 0 1 2 2 2
  line L175 (23.7251, -3.3976) -> (24.7192, -0.1927)
  line L176 (24.7192, -0.1927) -> (25.0074, -0.1927)
  line L177 (25.0074, -0.1927) -> (24.0174, -3.3976)
  line L178 (24.0174, -3.3976) -> (23.7251, -3.3976)
  spline S187 degree 2 poles (22.665, -0.6991) (22.9408, -0.6991) (23.3278, -0.8144) (23.4986, -0.8967) knots 0 0 0 1 2 2 2
  line L179 (23.4986, -0.8967) -> (23.4986, -1.3207)
  line L180 (23.4986, -1.3207) -> (23.4739, -1.3207)
  spline S188 degree 2 poles (23.4739, -1.3207) (23.3072, -1.1643) (22.8853, -0.9914) (22.6897, -0.9914) knots 0 0 0 1 2 2 2
  spline S189 degree 2 poles (22.6897, -0.9914) (22.4098, -0.9914) (22.1237, -1.224) (22.1237, -1.4154) knots 0 0 0 1 2 2 2
  spline S190 degree 2 poles (22.1237, -1.4154) (22.1237, -1.5677) (22.2739, -1.7571) (22.4365, -1.8044) knots 0 0 0 1 2 2 2
  spline S191 degree 2 poles (22.4365, -1.8044) (22.5539, -1.8374) (22.7494, -1.8826) (22.8956, -1.9197) knots 0 0 0 1 2 2 2
  spline S192 degree 2 poles (22.8956, -1.9197) (23.0273, -1.9547) (23.2352, -2.0597) (23.3155, -2.1441) knots 0 0 0 1 2 2 2
  spline S193 degree 2 poles (23.3155, -2.1441) (23.3937, -2.2285) (23.4801, -2.4549) (23.4801, -2.6031) knots 0 0 0 1 2 2 2
  spline S194 degree 2 poles (23.4801, -2.6031) (23.4801, -2.9118) (22.9985, -3.3297) (22.6259, -3.3297) knots 0 0 0 1 2 2 2
  spline S195 degree 2 poles (22.6259, -3.3297) (22.4118, -3.3297) (22.0331, -3.2453) (21.8705, -3.165) knots 0 0 0 1 2 2 2
  line L181 (21.8705, -3.165) -> (21.8705, -2.7616)
  line L182 (21.8705, -2.7616) -> (21.8952, -2.7616)
  spline S196 degree 2 poles (21.8952, -2.7616) (22.0166, -2.8727) (22.3954, -3.0374) (22.6033, -3.0374) knots 0 0 0 1 2 2 2
  spline S197 degree 2 poles (22.6033, -3.0374) (22.8379, -3.0374) (23.1281, -2.8171) (23.1281, -2.6381) knots 0 0 0 1 2 2 2
  spline S198 degree 2 poles (23.1281, -2.6381) (23.1281, -2.4775) (22.9573, -2.2861) (22.7968, -2.2429) knots 0 0 0 1 2 2 2
  spline S199 degree 2 poles (22.7968, -2.2429) (22.6897, -2.214) (22.3789, -2.1399) (22.276, -2.1091) knots 0 0 0 1 2 2 2
  spline S200 degree 2 poles (22.276, -2.1091) (22.0146, -2.0288) (21.7717, -1.7056) (21.7717, -1.4689) knots 0 0 0 1 2 2 2
  spline S201 degree 2 poles (21.7717, -1.4689) (21.7717, -1.3187) (21.8931, -1.0305) (22.0022, -0.9296) knots 0 0 0 1 2 2 2
  spline S202 degree 2 poles (22.0022, -0.9296) (22.1237, -0.8185) (22.4324, -0.6991) (22.665, -0.6991) knots 0 0 0 1 2 2 2
  line L183 (19.5857, -3.2844) -> (20.4605, -0.7444)
  line L184 (20.4605, -0.7444) -> (20.8249, -0.7444)
  line L185 (20.8249, -0.7444) -> (21.6997, -3.2844)
  line L186 (21.6997, -3.2844) -> (21.3374, -3.2844)
  line L187 (21.3374, -3.2844) -> (20.6334, -1.1746)
  line L188 (20.6334, -1.1746) -> (19.9295, -3.2844)
  line L189 (19.9295, -3.2844) -> (19.5857, -3.2844)
  line L190 (18.359, -3.3976) -> (19.3531, -0.1927)
  line L191 (19.3531, -0.1927) -> (19.6413, -0.1927)
  line L192 (19.6413, -0.1927) -> (18.6512, -3.3976)
  line L193 (18.6512, -3.3976) -> (18.359, -3.3976)
  line L194 (16.6402, -0.7444) -> (17.8794, -0.7444)
  line L195 (17.8794, -0.7444) -> (17.8794, -1.0037)
  line L196 (17.8794, -1.0037) -> (17.4183, -1.0037)
  line L197 (17.4183, -1.0037) -> (17.4183, -2.706)
  line L198 (17.4183, -2.706) -> (17.8794, -2.706)
  line L199 (17.8794, -2.706) -> (17.8794, -2.9386)
  spline S203 degree 2 poles (17.8794, -2.9386) (17.618, -2.9386) (17.3709, -3.0868) (17.3545, -3.2926) knots 0 0 0 1 2 2 2
  line L200 (17.3545, -3.2926) -> (17.091, -3.2926)
  line L201 (17.091, -3.2926) -> (17.091, -1.0037)
  line L202 (17.091, -1.0037) -> (16.6402, -1.0037)
  line L203 (16.6402, -1.0037) -> (16.6402, -0.7444)
  spline S204 degree 2 poles (16.243, -2.459) (16.243, -2.6545) (16.1154, -2.9797) (16.0042, -3.0971) knots 0 0 0 1 2 2 2
  spline S205 degree 2 poles (16.0042, -3.0971) (15.8992, -3.2103) (15.5925, -3.3358) (15.4361, -3.3358) knots 0 0 0 1 2 2 2
  spline S206 degree 2 poles (15.4361, -3.3358) (15.2611, -3.3358) (14.9771, -3.2185) (14.8721, -3.1074) knots 0 0 0 1 2 2 2
  spline S207 degree 2 poles (14.8721, -3.1074) (14.7404, -2.9674) (14.5963, -2.5146) (14.5963, -2.1667) knots 0 0 0 1 2 2 2
  spline S208 degree 2 poles (14.5963, -2.1667) (14.5963, -1.8518) (14.7383, -1.2878) (14.8762, -1.1005) knots 0 0 0 1 2 2 2
  spline S209 degree 2 poles (14.8762, -1.1005) (15.0224, -0.9029) (15.434, -0.695) (15.7346, -0.695) knots 0 0 0 1 2 2 2
  spline S210 degree 2 poles (15.7346, -0.695) (15.8025, -0.695) (15.9569, -0.7094) (16.0227, -0.73) knots 0 0 0 1 2 2 2
  line L204 (16.0227, -0.73) -> (16.0227, -1.0573)
  line L205 (16.0227, -1.0573) -> (16.0063, -1.0573)
  spline S211 degree 2 poles (16.0063, -1.0573) (15.963, -1.0326) (15.7819, -0.9893) (15.6893, -0.9893) knots 0 0 0 1 2 2 2
  spline S212 degree 2 poles (15.6893, -0.9893) (15.3558, -0.9893) (14.975, -1.4298) (14.9483, -1.8374) knots 0 0 0 1 2 2 2
  spline S213 degree 2 poles (14.9483, -1.8374) (15.0841, -1.7447) (15.3311, -1.6603) (15.4773, -1.6603) knots 0 0 0 1 2 2 2
  spline S214 degree 2 poles (15.4773, -1.6603) (15.6172, -1.6603) (15.8498, -1.7221) (15.9672, -1.8106) knots 0 0 0 1 2 2 2
  spline S215 degree 2 poles (15.9672, -1.8106) (16.103, -1.9156) (16.243, -2.2346) (16.243, -2.459) knots 0 0 0 1 2 2 2
  spline S216 degree 2 poles (14.94, -2.2429) (14.94, -2.5002) (15.0347, -2.8254) (15.1191, -2.9139) knots 0 0 0 1 2 2 2
  spline S217 degree 2 poles (15.1191, -2.9139) (15.1932, -2.9962) (15.3476, -3.058) (15.4382, -3.058) knots 0 0 0 1 2 2 2
  spline S218 degree 2 poles (15.4382, -3.058) (15.6481, -3.058) (15.8972, -2.7574) (15.8972, -2.4734) knots 0 0 0 1 2 2 2
  spline S219 degree 2 poles (15.8972, -2.4734) (15.8972, -2.3128) (15.8148, -2.105) (15.7243, -2.0309) knots 0 0 0 1 2 2 2
  spline S220 degree 2 poles (15.7243, -2.0309) (15.6584, -1.9773) (15.4958, -1.9423) (15.4011, -1.9423) knots 0 0 0 1 2 2 2
  spline S221 degree 2 poles (15.4011, -1.9423) (15.292, -1.9423) (15.0409, -2.0185) (14.9462, -2.0823) knots 0 0 0 1 2 2 2
  spline S222 degree 2 poles (14.9462, -2.0823) (14.9442, -2.107) (14.94, -2.1914) (14.94, -2.2429) knots 0 0 0 1 2 2 2
  line L206 (12.6326, -1.6171) -> (12.9352, -1.6171)
  line L207 (12.9352, -1.6171) -> (12.9352, -0.7444)
  line L208 (12.9352, -0.7444) -> (13.2625, -0.7444)
  line L209 (13.2625, -0.7444) -> (13.2625, -1.6171)
  line L210 (13.2625, -1.6171) -> (14.3843, -1.6171)
  line L211 (14.3843, -1.6171) -> (14.3843, -1.9753)
  line L212 (14.3843, -1.9753) -> (13.2481, -3.2844)
  line L213 (13.2481, -3.2844) -> (12.9352, -3.2844)
  line L214 (12.9352, -3.2844) -> (12.9352, -1.8909)
  line L215 (12.9352, -1.8909) -> (12.6326, -1.8909)
  line L216 (12.6326, -1.8909) -> (12.6326, -1.6171)
  line L217 (13.2625, -1.8909) -> (13.2625, -2.883)
  line L218 (13.2625, -2.883) -> (14.1167, -1.8909)
  line L219 (14.1167, -1.8909) -> (13.2625, -1.8909)
  spline S223 degree 2 poles (10.8213, -1.5513) (10.8213, -1.3681) (10.9386, -1.0552) (11.0456, -0.9399) knots 0 0 0 1 2 2 2
  spline S224 degree 2 poles (11.0456, -0.9399) (11.1527, -0.8247) (11.4717, -0.6909) (11.6693, -0.6909) knots 0 0 0 1 2 2 2
  spline S225 degree 2 poles (11.6693, -0.6909) (11.8505, -0.6909) (12.2045, -0.7711) (12.3342, -0.835) knots 0 0 0 1 2 2 2
  line L220 (12.3342, -0.835) -> (12.3342, -1.1952)
  line L221 (12.3342, -1.1952) -> (12.3095, -1.1952)
  spline S226 degree 2 poles (12.3095, -1.1952) (12.2704, -1.1663) (12.1242, -1.0922) (12.0357, -1.0593) knots 0 0 0 1 2 2 2
  spline S227 degree 2 poles (12.0357, -1.0593) (11.9349, -1.0243) (11.7681, -0.9852) (11.6632, -0.9852) knots 0 0 0 1 2 2 2
  spline S228 degree 2 poles (11.6632, -0.9852) (11.5602, -0.9852) (11.3668, -1.0593) (11.2968, -1.1396) knots 0 0 0 1 2 2 2
  spline S229 degree 2 poles (11.2968, -1.1396) (11.233, -1.2157) (11.1671, -1.4175) (11.1671, -1.5533) knots 0 0 0 1 2 2 2
  spline S230 degree 2 poles (11.1671, -1.5533) (11.1671, -1.6892) (11.2412, -1.8621) (11.3112, -1.9197) knots 0 0 0 1 2 2 2
  spline S231 degree 2 poles (11.3112, -1.9197) (11.3832, -1.9835) (11.5973, -2.037) (11.727, -2.037) knots 0 0 0 1 2 2 2
  spline S232 degree 2 poles (11.727, -2.037) (11.8669, -2.037) (12.1448, -1.9938) (12.2292, -1.9753) knots 0 0 0 1 2 2 2
  line L222 (12.2292, -1.9753) -> (12.2292, -3.2844)
  line L223 (12.2292, -3.2844) -> (10.8357, -3.2844)
  line L224 (10.8357, -3.2844) -> (10.8357, -2.9859)
  line L225 (10.8357, -2.9859) -> (11.9019, -2.9859)
  line L226 (11.9019, -2.9859) -> (11.9019, -2.3087)
  spline S233 degree 2 poles (11.9019, -2.3087) (11.8402, -2.317) (11.7208, -2.3231) (11.6714, -2.3231) knots 0 0 0 1 2 2 2
  spline S234 degree 2 poles (11.6714, -2.3231) (11.4758, -2.3231) (11.2062, -2.2593) (11.0827, -2.1646) knots 0 0 0 1 2 2 2
  spline S235 degree 2 poles (11.0827, -2.1646) (10.9571, -2.07) (10.8213, -1.7818) (10.8213, -1.5513) knots 0 0 0 1 2 2 2
  spline S236 degree 2 poles (10.5249, -2.459) (10.5249, -2.6545) (10.3973, -2.9797) (10.2861, -3.0971) knots 0 0 0 1 2 2 2
  spline S237 degree 2 poles (10.2861, -3.0971) (10.1811, -3.2103) (9.8744, -3.3358) (9.718, -3.3358) knots 0 0 0 1 2 2 2
  spline S238 degree 2 poles (9.718, -3.3358) (9.5431, -3.3358) (9.259, -3.2185) (9.154, -3.1074) knots 0 0 0 1 2 2 2
  spline S239 degree 2 poles (9.154, -3.1074) (9.0223, -2.9674) (8.8782, -2.5146) (8.8782, -2.1667) knots 0 0 0 1 2 2 2
  spline S240 degree 2 poles (8.8782, -2.1667) (8.8782, -1.8518) (9.0202, -1.2878) (9.1581, -1.1005) knots 0 0 0 1 2 2 2
  spline S241 degree 2 poles (9.1581, -1.1005) (9.3043, -0.9029) (9.716, -0.695) (10.0165, -0.695) knots 0 0 0 1 2 2 2
  spline S242 degree 2 poles (10.0165, -0.695) (10.0844, -0.695) (10.2388, -0.7094) (10.3046, -0.73) knots 0 0 0 1 2 2 2
  line L227 (10.3046, -0.73) -> (10.3046, -1.0573)
  line L228 (10.3046, -1.0573) -> (10.2882, -1.0573)
  spline S243 degree 2 poles (10.2882, -1.0573) (10.245, -1.0326) (10.0638, -0.9893) (9.9712, -0.9893) knots 0 0 0 1 2 2 2
  spline S244 degree 2 poles (9.9712, -0.9893) (9.6377, -0.9893) (9.2569, -1.4298) (9.2302, -1.8374) knots 0 0 0 1 2 2 2
  spline S245 degree 2 poles (9.2302, -1.8374) (9.366, -1.7447) (9.613, -1.6603) (9.7592, -1.6603) knots 0 0 0 1 2 2 2
  spline S246 degree 2 poles (9.7592, -1.6603) (9.8991, -1.6603) (10.1317, -1.7221) (10.2491, -1.8106) knots 0 0 0 1 2 2 2
  spline S247 degree 2 poles (10.2491, -1.8106) (10.3849, -1.9156) (10.5249, -2.2346) (10.5249, -2.459) knots 0 0 0 1 2 2 2
  spline S248 degree 2 poles (9.222, -2.2429) (9.222, -2.5002) (9.3166, -2.8254) (9.401, -2.9139) knots 0 0 0 1 2 2 2
  spline S249 degree 2 poles (9.401, -2.9139) (9.4751, -2.9962) (9.6295, -3.058) (9.7201, -3.058) knots 0 0 0 1 2 2 2
  spline S250 degree 2 poles (9.7201, -3.058) (9.93, -3.058) (10.1791, -2.7574) (10.1791, -2.4734) knots 0 0 0 1 2 2 2
  spline S251 degree 2 poles (10.1791, -2.4734) (10.1791, -2.3128) (10.0968, -2.105) (10.0062, -2.0309) knots 0 0 0 1 2 2 2
  spline S252 degree 2 poles (10.0062, -2.0309) (9.9403, -1.9773) (9.7777, -1.9423) (9.683, -1.9423) knots 0 0 0 1 2 2 2
  spline S253 degree 2 poles (9.683, -1.9423) (9.5739, -1.9423) (9.3228, -2.0185) (9.2281, -2.0823) knots 0 0 0 1 2 2 2
  spline S254 degree 2 poles (9.2281, -2.0823) (9.2261, -2.107) (9.222, -2.1914) (9.222, -2.2429) knots 0 0 0 1 2 2 2
  constraints: 2 end point, 1 perpendicular, 2 other
extrude "Extrusion2" cut sketch "Sketch2" against normal blind 1
sketch "Sketch3" plane through (0, -30, 0) normal (-1, 0, 0) x (0, 0, 1)
  line L0 (-70.75, -52) -> (-70.75, -23) projected
  line L1 (-70.75, -23) -> (-65.75, -23) projected
  line L2 (-65.75, -23) -> (-65.75, -52) projected
  line L3 (-65.75, -52) -> (-70.75, -52) projected
  line L4 (-19.25, -52) -> (-19.25, -23) projected
  line L5 (-19.25, -23) -> (-14.25, -23) projected
  line L6 (-14.25, -23) -> (-14.25, -52) projected
  line L7 (-14.25, -52) -> (-19.25, -52) projected
  circle A0 centre (-62.3489, -48.25) radius 1.25 projected
  circle A1 centre (-62.3489, -26.25) radius 1.25 projected
  circle A2 centre (-38.3489, -48.25) radius 1 projected
  circle A3 centre (-22.3489, -48.25) radius 1.25 projected
  circle A4 centre (-22.3489, -26.25) radius 1.25 projected
  circle A5 centre (-38.3489, -26.25) radius 1 projected
  circle A6 centre (-30.3489, -37.25) radius 10.75 projected
  line L8 (-75, -57) -> (-19.3875, -57) projected
  arc A7 (-19.3875, -57) -> (-15.1335, -54.6275) centre (-19.3875, -52) ccw projected
  line L9 (-15.1335, -54.6275) -> (0, -30.1255) projected
  line L10 (0, -30.1255) -> (0, 30) projected
  line L11 (0, 30) -> (-16.0989, 30) projected
  line L12 (-16.0989, 30) -> (-16.0989, 35) projected
  line L13 (-16.0989, 35) -> (-26.0989, 35) projected
  line L14 (-26.0989, 35) -> (-26.0989, 30) projected
  line L15 (-26.0989, 30) -> (-36.0989, 30) projected
  line L16 (-36.0989, 30) -> (-36.0989, 35) projected
  line L17 (-36.0989, 35) -> (-43.5989, 35) projected
  line L18 (-43.5989, 35) -> (-43.5989, 30) projected
  line L19 (-43.5989, 30) -> (-53.5989, 30) projected
  line L20 (-53.5989, 30) -> (-53.5989, 35) projected
  line L21 (-53.5989, 35) -> (-63.5989, 35) projected
  line L22 (-63.5989, 35) -> (-63.5989, 30) projected
  line L23 (-63.5989, 30) -> (-95, 30) projected
  line L24 (-95, 30) -> (-95, -37) projected
  arc A8 (-95, -37) -> (-75, -57) centre (-75, -37) ccw projected
  line L25 (-3, -5) -> (-3, 0) projected
  line L26 (0, 0) -> (-3, 0) projected
  line L27 (0, -5) -> (0, 0)
  line L28 (-3, -5) -> (-3, 0) projected
  line L29 (0, 0) -> (-3, 0)
  line L30 (0, -5) -> (-3, -5) projected
  line L31 (0, -5) -> (-14.25, -23)
  line L32 (0, -5) -> (-3, -5) projected
  line L33 (-3, -5) -> (-19.25, -23)
  line L34 (-26.5, -19) -> (-54.5, -19) projected
  line L35 (-54.5, -19) -> (-54.5, -7) projected
  line L36 (-54.5, -7) -> (-26.5, -7) projected
  line L37 (-26.5, -7) -> (-26.5, -19) projected
  constraints: 8 end point, 2 perpendicular
ref_plane "Work Plane1" through (124, -87, -95) normal (1, 0, 0) x (0, 1, 0)
extrude "Extrusion3" add sketch "Sketch3" against normal up to surface (124 mm away) contours L33 L30 L31 L5 | L25 L26 L10 L30
body "Solid1"
